Target (Autodesk Fusion 360 design; units mm, degrees)
part number: 2026-10-17-16-48-15-145
Autodesk Fusion 360 part; units mm, degrees
sketch "Sketch1" plane through (0, 0, 0) normal (0, 0, 1) x (1, 0, 0)
  circle A0 centre (0, 0) radius 300
  dimension "d1" = 600
  constraint coincident A0.centre origin
  measures "d1" diameter of A0
extrude "Extrude1" add sketch "Sketch1" along normal blind 1
sketch "Sketch2" plane through (0, 0, 1) normal (0, 0, 1) x (-1, 0, 0)
  circle A0 centre (0, 0) radius 300
  circle A1 centre (0, 0) radius 240
  circle A2 centre (0, 0) radius 180
  circle A3 centre (0, 0) radius 120
  circle A4 centre (0, 0) radius 60
  dimension "d4" = 480
  dimension "d5" = 360
  dimension "d6" = 240
  dimension "d7" = 120
  constraint coincident A0.centre A1.centre
  constraint concentric A1 A2
  constraint concentric A2 A3
  constraint concentric A3 A4
  measures "d4" diameter of A1
  measures "d5" diameter of A2
  measures "d6" diameter of A3
  measures "d7" diameter of A4
extrude "Extrude4" add sketch "Sketch2" along normal blind 10 contours A0
extrude "Extrude5" add sketch "Sketch2" along normal blind 8 contours A1
extrude "Extrude6" add sketch "Sketch2" along normal blind 6 contours A2
extrude "Extrude7" add sketch "Sketch2" along normal blind 4 contours A3
